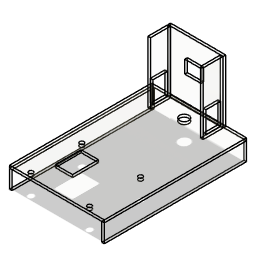
1 (Autodesk Fusion 360 archive; units mm, degrees)
design "placa de acrilico"
Autodesk Fusion 360 part; units mm, degrees
sketch "Esboço1" plane through (0, 0, 0) normal (0, 1, 0) x (1, 0, 0)
  line L0 (0, 0) -> (110, 0)
  line L1 (110, 0) -> (110, 165)
  line L2 (110, 165) -> (0, 165)
  line L3 (0, 165) -> (0, 0)
  circle A0 centre (53.9406, 148.8389) radius 5.4
  line L4 (46.0554, 27.0704) -> (26.0554, 27.0704)
  line L5 (26.0554, 27.0704) -> (26.0554, 57.0704)
  line L6 (26.0554, 57.0704) -> (46.0554, 57.0704)
  line L7 (46.0554, 57.0704) -> (46.0554, 27.0704)
  circle A1 centre (87.4376, 5.4927) radius 2.5
  circle A2 centre (19.4847, 5.405) radius 2.5
  circle A3 centre (19.4835, 64.4469) radius 2.5
  circle A4 centre (87.474, 64.6425) radius 2.5
  dimension "d1" = 110
  dimension "d2" = 165
  dimension "d4" = 10.8
  dimension "d9" = 20
  dimension "d10" = 30
  dimension "d13" = 5
  dimension "d16" = 5
  dimension "d19" = 5
  dimension "d23" = 5
  constraint horizontal L0
  constraint vertical L1
  constraint horizontal L2
  constraint vertical L3
  constraint coincident L0.start L3.end
  constraint horizontal L4
  constraint vertical L5
  constraint horizontal L6
  constraint vertical L7
  measures "d1" distance of L0.start L0.end
  measures "d2" distance of L0.start L2.end
  measures "d4" diameter of A0
  measures "d9" distance of L4.start L4.end
  measures "d10" distance of L4.end L5.end
  measures "d13" diameter of A1
  measures "d16" diameter of A2
  measures "d19" diameter of A3
  measures "d23" diameter of A4
extrude "Extrusão1" add sketch "Esboço1" along normal blind 3 makes body 1
sketch "Esboço2" plane through (0, 0, 0) normal (0, 1, 0) x (1, 0, 0)
  line L0 (120, 0) -> (141, 0)
  line L1 (141, 0) -> (141, 165)
  line L2 (141, 165) -> (120, 165)
  line L3 (120, 165) -> (120, 0)
  dimension "d26" = 21
  dimension "d27" = 165
  constraint horizontal L0
  constraint vertical L1
  constraint horizontal L2
  constraint vertical L3
  measures "d26" distance of L0.start L0.end
  measures "d27" distance of L0.end L1.end
extrude "Extrusão2" add sketch "Esboço2" along normal blind 3 separate body makes body 2
sketch "Esboço3" plane through (0, 0, 0) normal (0, 1, 0) x (1, 0, 0)
  line L0 (150, 0) -> (171, 0)
  line L1 (171, 0) -> (171, 165)
  line L2 (171, 165) -> (150, 165)
  line L3 (150, 165) -> (150, 0)
  dimension "d30" = 21
  dimension "d31" = 165
  constraint horizontal L0
  constraint vertical L1
  constraint horizontal L2
  constraint vertical L3
  measures "d30" distance of L0.start L0.end
  measures "d31" distance of L0.start L2.end
extrude "Extrusão3" add sketch "Esboço3" along normal blind 3 separate body makes body 3
move_body "Mover1" bodies 3 to x (0, -1, 0) y (1, 0, 0) z (0, 0, 1) at (0.0251, 149.951, 0.0481)
move_body "Mover2" bodies 2 to x (0, -1, 0) y (1, 0, 0) z (0, 0, 1) at (107.0123, 119.9798, 0)
sketch "Esboço4" plane through (0, 0, 0) normal (0, 1, 0) x (1, 0, 0)
  line L0 (0.0988, 170.3714) -> (22.0988, 170.3714)
  line L1 (22.0988, 170.3714) -> (86.0988, 170.3714)
  line L2 (86.0988, 170.3714) -> (86.0988, 242.3714)
  line L3 (22.0988, 170.3714) -> (22.0988, 242.3714)
  line L4 (22.0988, 242.3714) -> (86.0988, 242.3714)
  line L5 (41.605, 217.3714) -> (60.605, 217.3714)
  line L6 (41.605, 217.3714) -> (41.605, 202.3714)
  line L7 (60.605, 217.3714) -> (60.605, 202.3714)
  line L8 (41.605, 202.3714) -> (60.605, 202.3714)
  dimension "d34" = 22
  dimension "d35" = 64
  dimension "d36" = 72
  dimension "d37" = 72
  dimension "d44" = 19
  dimension "d46" = 15
  dimension "d47" = 15
  constraint horizontal L0
  constraint parallel L0 L1
  constraint perpendicular L1 L2
  constraint perpendicular L0 L3
  constraint perpendicular L5 L6
  constraint perpendicular L5 L7
  measures "d34" distance of L0.start L0.end
  measures "d35" distance of L0.end L1.end
  measures "d36" distance of L1.end L2.end
  measures "d37" distance of L0.end L3.end
  measures "d44" distance of L5.start L5.end
  measures "d46" distance of L5.start L6.end
  measures "d47" distance of L5.end L7.end
extrude "Extrusão4" add sketch "Esboço4" along normal blind 3 separate body makes body 4
move_body "Mover3" bodies 4 to x (1, 0, 0) y (0, 1, 0) z (0, 0, 1) at (0, 0, 5.0419)
move_body "Mover4" bodies 4 to x (1, 0, 0) y (0, 1, 0) z (0, 0, 1) at (0, 0, 0.1848)
sketch "Esboço5" plane through (0, 3, 0) normal (0, 1, 0) x (-1, 0, 0)
  line L0 (-41.605, -197.1446) -> (-41.605, -212.1446)
  line L1 (-41.605, -212.1446) -> (-60.605, -212.1446)
  line L2 (-60.605, -212.1446) -> (-60.605, -197.1446)
  line L3 (-60.605, -197.1446) -> (-41.605, -197.1446)
  line L4 (-22.0988, -165.1446) -> (-86.0988, -165.1446)
  line L5 (-86.0988, -165.1446) -> (-86.0988, -237.1446)
  line L6 (-86.0988, -237.1446) -> (-22.0988, -237.1446)
  line L7 (-22.0988, -237.1446) -> (-22.0988, -165.1446)
  line L8 (-159.9044, -164.752) -> (-182.9044, -164.752)
  line L9 (-182.9044, -164.752) -> (-182.9044, -236.752)
  line L10 (-182.9044, -236.752) -> (-159.9044, -236.752)
  line L11 (-159.9044, -236.752) -> (-159.9044, -164.752)
  line L12 (-163.1314, -168.0719) -> (-180.1314, -168.0719)
  line L13 (-180.1314, -168.0719) -> (-180.1314, -193.0719)
  line L14 (-180.1314, -193.0719) -> (-163.1314, -193.0719)
  line L15 (-163.1314, -193.0719) -> (-163.1314, -168.0719)
  line L16 (-144.4837, -168.5234) -> (-144.4837, -240.5234)
  line L17 (-121.4837, -240.5234) -> (-121.4837, -168.5234)
  line L18 (-141.7107, -171.8432) -> (-141.7107, -196.8432)
  line L19 (-124.7107, -171.8432) -> (-141.7107, -171.8432)
  line L20 (-141.7107, -196.8432) -> (-124.7107, -196.8432)
  line L21 (-121.4837, -168.5234) -> (-144.4837, -168.5234)
  line L22 (-144.4837, -240.5234) -> (-121.4837, -240.5234)
  line L23 (-124.7107, -196.8432) -> (-124.7107, -171.8432)
  dimension "d50" = 23
  dimension "d51" = 72
  dimension "d55" = 17
  dimension "d56" = 25
  dimension "d57" = 23
  dimension "d58" = 72
  dimension "d59" = 17
  dimension "d60" = 25
  constraint horizontal L8
  constraint vertical L9
  constraint horizontal L10
  constraint vertical L11
  constraint horizontal L12
  constraint vertical L13
  constraint horizontal L14
  constraint vertical L15
  constraint horizontal L21
  constraint vertical L16
  constraint horizontal L22
  constraint vertical L17
  constraint horizontal L19
  constraint vertical L18
  constraint horizontal L20
  constraint vertical L23
  measures "d50" distance of L8.start L8.end
  measures "d51" distance of L8.start L10.end
  measures "d55" distance of L12.start L12.end
  measures "d56" distance of L12.start L14.end
  measures "d57" distance of L16.start L17.end
  measures "d58" distance of L17.end L17.start
  measures "d59" distance of L18.start L19.start
  measures "d60" distance of L19.start L20.end
extrude "Extrusão5" add sketch "Esboço5" along normal blind 3 separate body contours L8 L9 L10 L11 makes body 5
extrude "Extrusão6" add sketch "Esboço5" along normal blind 3 separate body contours L16 L17 L21 L22 makes body 6
move_body "Mover5" bodies 5 to x (0, 1, 0) y (-1, 0, 0) z (0, 0, 1) at (27.3401, -183.0555, -0.1604)
move_body "Mover6" bodies 5 to x (1, 0, 0) y (0, 1, 0) z (0, 0, 1) at (0.7325, 0, -0.2616)
move_body "Mover7" bodies 5 to x (1, 0, 0) y (0, 1, 0) z (0, 0, 1) at (-0.0523, 0.157, 0)
move_body "Mover8" bodies 6 to x (0, -1, 0) y (1, 0, 0) z (0, 0, 1) at (83.0995, 124.4103, 3.4941)
move_body "Mover9" bodies 4 5 6 to x (1, 0, 0) y (0, 0, 1) z (0, -1, 0) at (-0.3031, -161.9207, -141.7867)
move_body "Mover10" bodies 6 to x (1, 0, 0) y (0, 1, 0) z (0, 0, 1) at (0, 2.7335, -4.2826)
move_body "Mover11" bodies 6 to x (1, 0, 0) y (0, 1, 0) z (0, 0, 1) at (0, -2.6483, 1.4345)
move_body "Mover12" bodies 3 5 1 6 2 4 to x (1, 0, 0) y (0, 1, 0) z (0, 0, 1) at (135.7751, 64.3146, 24.9729)
move_body "Mover13" bodies 6 to x (1, 0, 0) y (0, 1, 0) z (0, 0, 1) at (-3.0347, -0.002, 26.0381)
move_body "Mover14" bodies 5 to x (1, 0, 0) y (0, 1, 0) z (0, 0, 1) at (0, -0.2162, 26.1575)
move_body "Mover15" bodies 5 4 6 to x (1, 0, 0) y (0, 1, 0) z (0, 0, 1) at (0.1081, -0.9435, -23.1586)
copy_body "Corpo -> Componente1" bodies 1 removing the originals makes body 7 in component "Component"
copy_body "Corpo -> Componente2" bodies 2 removing the originals makes body 8 in component "Component'"
copy_body "Corpo -> Componente3" bodies 3 removing the originals makes body 9 in component "Component''"
copy_body "Corpo -> Componente4" bodies 4 removing the originals makes body 10 in component "Component'''"
copy_body "Corpo -> Componente5" bodies 5 removing the originals makes body 11 in component "Component''''"
copy_body "Corpo -> Componente6" bodies 6 removing the originals makes body 12 in component "Component'''''"
component "Component" placed x (1, 0, 0) y (0, 1, 0) z (0, 0, 1) at (0, 0, 0)
component "Component'" placed x (1, 0, 0) y (0, 1, 0) z (0, 0, 1) at (0, 0, 0)
component "Component''" placed x (1, 0, 0) y (0, 1, 0) z (0, 0, 1) at (0, 0, 0)
component "Component'''" placed x (1, 0, 0) y (0, 1, 0) z (0, 0, 1) at (0, 0, 0)
component "Component''''" placed x (1, 0, 0) y (0, 1, 0) z (0, 0, 1) at (0, 0, 0)
component "Component'''''" placed x (1, 0, 0) y (0, 1, 0) z (0, 0, 1) at (0, 0, 0)

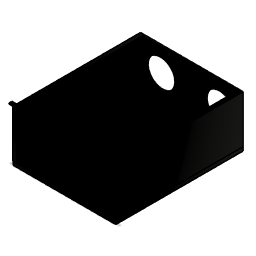
design "case ultrassonico"
Autodesk Fusion 360 part; units mm, degrees
sketch "Esboço1" plane through (0, 0, 0) normal (0, 1, 0) x (1, 0, 0)
  line L0 (0, 0) -> (50, 0)
  line L1 (0, 0) -> (0, 25)
  line L2 (0, 25) -> (50, 25)
  line L3 (50, 0) -> (50, 25)
  dimension "d1" = 50
  dimension "d2" = 25
  dimension "d3" = 50
  constraint coincident L0.start L1.start
  constraint horizontal L0
  constraint perpendicular L0 L1
  constraint perpendicular L1 L2
  measures "d1" distance of L0.start L0.end
  measures "d2" distance of L0.start L1.end
  measures "d3" distance of L1.end L2.end
extrude "Extrusão1" add sketch "Esboço1" along normal blind 1 makes body 1
hole "Furo1" at (48.8081, 0, -23.5629) direction (0, 1, 0) diameter 1.8 depth 3 tip angle 118 bodies 1
hole "Furo2" at (1.4563, 0, -23.59) direction (0, 1, 0) diameter 1.8 depth 3 tip angle 118 bodies 1
hole "Furo3" at (1.4485, 0, -1.5957) direction (0, 1, 0) diameter 1.8 depth 3 tip angle 118 bodies 1
hole "Furo4" at (48.7733, 0, -1.5876) direction (0, 1, 0) diameter 1.8 depth 3 tip angle 118 bodies 1
hole "Furo5" at (40.5295, 1, -12.6422) direction (0, -1, 0) diameter 15 depth 3 tip angle 118 bodies 1
hole "Furo6" at (9.5185, 1, -12.5143) direction (0, -1, 0) diameter 15 depth 3 tip angle 118 bodies 1
sketch "Esboço2" plane through (0, 0, 0) normal (0, 1, 0) x (1, 0, 0)
hole "Furo7" at (19.0736, 1, -6.6825) direction (0, -1, 0) diameter 2 depth 3 tip angle 118 bodies 1
hole "Furo8" at (21.3988, 1, -6.6049) direction (0, -1, 0) diameter 2 depth 3 tip angle 118 bodies 1
hole "Furo9" at (23.8843, 1, -6.6851) direction (0, -1, 0) diameter 2 depth 3 tip angle 118 bodies 1
hole "Furo10" at (26.4099, 1, -6.7252) direction (0, -1, 0) diameter 2 depth 3 tip angle 118 bodies 1
sketch "Esboço3" plane through (0, 0, 0) normal (0, 1, 0) x (1, 0, 0)
  line L0 (0, -40) -> (67.2, -40)
  line L1 (0, 25) -> (0, 0)
  line L2 (0, -40) -> (0, -15)
  line L3 (0, -15) -> (67.2, -15)
  line L4 (67.2, -15) -> (67.2, -40)
  line L5 (4.8529, -44.5004) -> (72.0529, -44.5004)
  line L6 (4.8529, -69.5004) -> (72.0529, -69.5004)
  line L7 (4.8529, -44.5004) -> (4.8529, -69.5004)
  line L8 (72.0529, -44.5004) -> (72.0529, -69.5004)
  dimension "d37" = 25
  dimension "d38" = 25
  dimension "d39" = 67.2
  dimension "d40" = 25
  dimension "d41" = 67.2
  constraint horizontal L0
  constraint perpendicular L0 L2
  constraint perpendicular L2 L3
  constraint horizontal L6
  constraint perpendicular L6 L7
  constraint perpendicular L6 L8
  measures "d37" distance of L1.start L1.end
  measures "d38" distance of L0.start L2.end
  measures "d39" distance of L2.end L3.end
  measures "d40" distance of L5.start L6.start
  measures "d41" distance of L5.start L5.end
extrude "Extrusão2" add sketch "Esboço3" along normal blind 2 separate body contours L0 L2 L3 L4 makes body 2
extrude "Extrusão3" add sketch "Esboço3" along normal blind 2 separate body contours L5 L6 L7 L8 makes body 3
move_body "Mover1" bodies 1 to x (1, 0, 0) y (0, 0, 1) z (0, -1, 0) at (0, -1.7077, -25.5977)
move_body "Mover2" bodies 3 to x (0, 0, -1) y (-1, 0, 0) z (0, 1, 0) at (-0.0034, -46.234, 46.4307)
move_body "Mover3" bodies 2 to x (0, 0, -1) y (1, 0, 0) z (0, -1, 0) at (50.0007, 38.304, 41.6132)
sketch "Esboço4" plane through (0, 0, 0) normal (0, 1, 0) x (1, 0, 0)
  line L0 (-40, 0) -> (-40, 10)
  line L1 (-40, 10) -> (-30, 10)
  line L2 (-30, 10) -> (-30, 5)
  line L3 (-30, 5) -> (-35, 5)
  line L4 (-35, 5) -> (-35, 0)
  line L5 (-35, 0) -> (-40, 0)
  constraint vertical L0
  constraint perpendicular L0 L1
  constraint perpendicular L1 L2
  constraint perpendicular L2 L3
  constraint perpendicular L3 L4
  constraint perpendicular L0 L5
sketch "Esboço5" plane through (0, 0, 0) normal (0, 1, 0) x (1, 0, 0)
  line L0 (-4.2157, -41.4575, -0.4132) -> (-8.1992, -41.4575, -0.4132)
  line L1 (-8.1992, -41.4575, -0.4132) -> (-8.1992, -39.8904, -0.4132)
  line L2 (-8.1992, -39.8904, -0.4132) -> (-4.1992, -39.8904, -0.4132)
  line L3 (-4.1992, -39.8904, -0.4132) -> (-4.2157, -41.4575, -0.4132)
  dimension "d48" = 3.9836
  dimension "d49" = 1.5671
extrude "Extrusão5" add sketch "Esboço5" along normal blind 0.5 separate body contours L0 L1 L2 L3 in plane through (0, -0.4132, 0) normal (0, 1, 0) makes body 4
move_body "Mover5" bodies 4 to x (1, 0, 0) y (0, 1, 0) z (0, 0, 1) at (4.2199, 23.6968, 0.1453)
sketch "Esboço6" plane through (0, 0, 0) normal (0, 1, 0) x (1, 0, 0)
  line L0 (50.0163, -44.0903) -> (54.0003, -44.0903)
  line L1 (50.0163, -44.0903) -> (50.0163, -42.5233)
  line L2 (50.0163, -42.5233) -> (53.9855, -42.5233)
  line L3 (53.9855, -42.5233) -> (54.0003, -44.0903)
  dimension "d52" = 3.984
  dimension "d53" = 1.567
  constraint horizontal L0
  constraint perpendicular L0 L1
  constraint perpendicular L1 L2
  measures "d52" distance of L0.start L0.end
  measures "d53" distance of L0.start L1.end
extrude "Extrusão6" add sketch "Esboço6" along normal blind 0.5 separate body makes body 5
move_body "Mover6" bodies 5 to x (1, 0, 0) y (0, 1, 0) z (0, 0, 1) at (-0.0037, 23.3, -2.5739)
move_body "Mover7" bodies 5 to x (1, 0, 0) y (0, 1, 0) z (0, 0, 1) at (-0.0106, 0, 0.0823)
sketch "Esboço7" plane through (0, 0, 0) normal (0, 1, 0) x (1, 0, 0)
  line L0 (0, 25.5977) -> (50, 25.5977)
  line L1 (52.0007, -41.6132) -> (52.0007, 25.5868)
  line L2 (70, 0) -> (120, 0)
  line L3 (120, 0) -> (120, -67.2)
  line L4 (120, -67.2) -> (70, -67.2)
  line L5 (70, -67.2) -> (70, 0)
  dimension "d56" = 50
  dimension "d57" = 67.2
  dimension "d58" = 67.2
  dimension "d59" = 50
  constraint horizontal L2
  constraint vertical L3
  constraint horizontal L4
  constraint vertical L5
  measures "d56" distance of L0.start L0.end
  measures "d57" distance of L1.start L1.end
  measures "d58" distance of L2.start L4.end
  measures "d59" distance of L2.start L2.end
sketch "Esboço8" plane through (0, 0, 0) normal (0, 1, 0) x (1, 0, 0)
  line L0 (-30, 0) -> (-84, 0)
  line L1 (-84, 0) -> (-84, 67)
  line L2 (-84, 67) -> (-30, 67)
  line L3 (-30, 67) -> (-30, 0)
  dimension "d66" = 67
  dimension "d67" = 54
  constraint horizontal L0
  constraint vertical L1
  constraint horizontal L2
  constraint vertical L3
  measures "d66" distance of L0.start L2.end
  measures "d67" distance of L0.start L0.end
extrude "Extrusão8" add sketch "Esboço8" along normal blind 2 separate body makes body 6
move_body "Mover10" bodies 6 to x (1, 0, 0) y (0, 1, 0) z (0, 0, 1) at (82.019, -3.6652, 41.4629)
copy_body "Corpo -> Componente1" bodies 1 removing the originals makes body 7 in component "Component"
copy_body "Corpo -> Componente2" bodies 2 removing the originals makes body 8 in component "Component'"
copy_body "Corpo -> Componente3" bodies 3 removing the originals makes body 9 in component "Component''"
copy_body "Corpo -> Componente4" bodies 4 removing the originals makes body 10 in component "Component'''"
copy_body "Corpo -> Componente5" bodies 5 removing the originals makes body 11 in component "Component''''"
copy_body "Corpo -> Componente6" bodies 6 removing the originals makes body 12 in component "Component'''''"
move_body "Mover1'" bodies 9 to x (1, 0, 0) y (0, 1, 0) z (0, 0, 1) at (165.5243, 14.3172, -24.596) in component "Component''"
move_body "Mover1''" bodies 11 to x (1, 0, 0) y (0, 1, 0) z (0, 0, 1) at (165.5243, 14.3172, -24.596) in component "Component''''"
move_body "Mover1'''" bodies 12 to x (1, 0, 0) y (0, 1, 0) z (0, 0, 1) at (165.5243, 14.3172, -24.596) in component "Component'''''"
move_body "Mover1''''" bodies 10 to x (1, 0, 0) y (0, 1, 0) z (0, 0, 1) at (165.5243, 14.3172, -24.596) in component "Component'''"
move_body "Mover1'''''" bodies 8 to x (1, 0, 0) y (0, 1, 0) z (0, 0, 1) at (165.5243, 14.3172, -24.596) in component "Component'"
move_body "Mover1''''''" bodies 7 to x (1, 0, 0) y (0, 1, 0) z (0, 0, 1) at (165.5243, 14.3172, -24.596) in component "Component"
component "Component" placed x (1, 0, 0) y (0, 1, 0) z (0, 0, 1) at (0, 0, 0)
component "Component'" placed x (1, 0, 0) y (0, 1, 0) z (0, 0, 1) at (0, 0, 0)
component "Component''" placed x (1, 0, 0) y (0, 1, 0) z (0, 0, 1) at (0, 0, 0)
component "Component'''" placed x (1, 0, 0) y (0, 1, 0) z (0, 0, 1) at (0, 0, 0)
component "Component''''" placed x (1, 0, 0) y (0, 1, 0) z (0, 0, 1) at (0, 0, 0)
component "Component'''''" placed x (1, 0, 0) y (0, 1, 0) z (0, 0, 1) at (0, 0, 0)

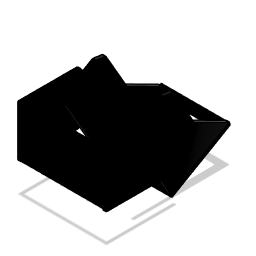
design "estrutura da camera"
Autodesk Fusion 360 part; units mm, degrees
sketch "Esboço1" plane through (0, 0, 0) normal (0, 1, 0) x (1, 0, 0)
  line L0 (0, 0) -> (0, 25.6)
  line L1 (0, 25.6) -> (30, 25.6)
  line L2 (30, 25.6) -> (35.5763, 17.2991)
  line L3 (35.5763, 17.2991) -> (35.5763, 7.2991)
  line L4 (35.5763, 7.2991) -> (28.6904, 0.0476)
  line L5 (0, 0) -> (28.6904, 0.0476)
  line L6 (0.2721, -30.9273) -> (0.2721, -5.3273)
  line L7 (35.8484, -13.6282) -> (35.8484, -23.6282)
  line L8 (30.2721, -5.3273) -> (35.8484, -13.6282)
  line L9 (35.8484, -23.6282) -> (28.9625, -30.8797)
  line L10 (0.2721, -5.3273) -> (30.2721, -5.3273)
  line L11 (0.2721, -30.9273) -> (28.9625, -30.8797)
  point P0 (0.2721, -30.9273)
  dimension "d1" = 25.6
  dimension "d13" = 30
  dimension "d14" = 10
  dimension "d15" = 10
  dimension "d16" = 10
  dimension "d17" = 25.6
  dimension "d18" = 30
  dimension "d19" = 10
  dimension "d20" = 10
  dimension "d21" = 10
  constraint coincident L0.start L5.start
  constraint vertical L0
  constraint perpendicular L0 L1
  constraint perpendicular L1 L3
  constraint coincident P0 L6.start
  constraint vertical L6
  constraint perpendicular L6 L10
  constraint perpendicular L7 L10
  measures "d1" distance of L0.start L0.end
  measures "d13" distance of L0.end L1.end
  measures "d14" distance of L1.end L2.end
  measures "d15" distance of L2.end L3.end
  measures "d16" distance of L3.end L4.end
  measures "d17" distance of P0 L6.end
  measures "d18" distance of L8.start L6.end
  measures "d19" distance of L8.start L7.start
  measures "d20" distance of L7.start L7.end
  measures "d21" distance of L9.end L7.end
extrude "Extrusão1" add sketch "Esboço1" along normal blind 1.7 contours L0 L1 L2 L3 L4 L5 makes body 1
extrude "Extrusão2" add sketch "Esboço1" along normal blind 1.7 separate body contours L6 L7 L8 L9 L10 L11 makes body 2
sketch "Esboço2" plane through (0, 0, 0) normal (0, 1, 0) x (1, 0, 0)
  line L0 (50, 0) -> (94.3, 0)
  line L1 (94.3, 0) -> (94.3, 25)
  line L2 (94.3, 25) -> (50, 25)
  line L3 (50, 25) -> (50, 0)
  dimension "d26" = 44.3
  dimension "d27" = 25
  constraint horizontal L0
  constraint vertical L1
  constraint horizontal L2
  constraint vertical L3
  measures "d26" distance of L0.start L0.end
  measures "d27" distance of L0.start L2.end
extrude "Extrusão3" add sketch "Esboço2" along normal blind 1.7 separate body makes body 3
move_body "Mover1" bodies 2 to x (0, 0, 1) y (1, 0, 0) z (0, 1, 0) at (14.9891, -4.8114, 5.0553)
move_body "Mover2" bodies 3 to x (1, 0, 0) y (0, 0, 1) z (0, -1, 0) at (-35.3599, 1.1388, 5.3832)
move_body "Mover3" bodies 3 to x (1, 0, 0) y (0, 1, 0) z (0, 0, 1) at (0.6743, -0.0545, 0)
move_body "Mover4" bodies 1 to x (0, 0, 1) y (-1, 0, 0) z (0, -1, 0) at (59.6914, 0.4143, 4.9875)
move_body "Mover5" bodies 1 to x (1, 0, 0) y (0, 1, 0) z (0, 0, 1) at (0, 0.3354, 0.5385)
sketch "Esboço3" plane through (0, 0, 0) normal (0, 1, 0) x (1, 0, 0)
  line L0 (-26.5558, -20.9139) -> (7.4442, -20.9139)
  line L1 (7.4442, -20.9139) -> (7.4442, 13.0861)
  line L2 (7.4442, 13.0861) -> (-26.5558, 13.0861)
  line L3 (-26.5558, 13.0861) -> (-26.5558, -20.9139)
  line L4 (-22.5558, -16.9139) -> (3.21, -16.9139)
  line L5 (-22.5558, -16.9139) -> (-22.5558, 9.1437)
  line L6 (-22.5558, 9.1437) -> (3.21, 9.0861)
  line L7 (3.21, -16.9139) -> (3.21, 9.0861)
  dimension "d30" = 34
  dimension "d31" = 34
  constraint horizontal L0
  constraint vertical L1
  constraint horizontal L2
  constraint vertical L3
  constraint perpendicular L3 L4
  constraint vertical L7
  measures "d30" distance of L0.start L0.end
  measures "d31" distance of L0.start L2.end
extrude "Extrusão4" add sketch "Esboço3" along normal blind 1.7 separate body makes body 4
sketch "Esboço4" plane through (0, 0, 0) normal (0, 1, 0) x (1, 0, 0)
  line L0 (68.4509, 0.0237) -> (102.4509, 0.0237)
  line L1 (68.4509, 0.0237) -> (68.4509, 38.0237)
  line L2 (68.4509, 38.0237) -> (72.4483, 41.0271)
  line L3 (72.4483, 41.0271) -> (87.4483, 41.0271)
  line L4 (87.4483, 41.0271) -> (91.3736, 37.93)
  line L5 (91.3736, 37.93) -> (91.3736, 16.93)
  line L6 (102.4509, 0.0237) -> (91.3736, 16.93)
  line L7 (109.5977, 1.8719) -> (109.5977, 39.8719)
  line L8 (109.5977, 1.8719) -> (143.5977, 1.8719)
  line L9 (109.5977, 39.8719) -> (113.5952, 42.8753)
  line L10 (132.5204, 39.7782) -> (132.5204, 18.7782)
  line L11 (113.5952, 42.8753) -> (128.5952, 42.8753)
  line L12 (143.5977, 1.8719) -> (132.5204, 18.7782)
  line L13 (128.5952, 42.8753) -> (132.5204, 39.7782)
  dimension "d38" = 34
  dimension "d45" = 38
  dimension "d46" = 5
  dimension "d47" = 15
  dimension "d48" = 5
  dimension "d49" = 21
  dimension "d50" = 20.212
  dimension "d51" = 34
  dimension "d52" = 38
  dimension "d53" = 5
  dimension "d54" = 15
  dimension "d55" = 5
  dimension "d56" = 21
  dimension "d57" = 20.212
  constraint horizontal L0
  constraint perpendicular L0 L1
  constraint horizontal L3
  constraint perpendicular L3 L5
  constraint horizontal L8
  constraint perpendicular L7 L8
  constraint horizontal L11
  constraint perpendicular L10 L11
  measures "d38" distance of L0.start L0.end
  measures "d45" distance of L0.start L1.end
  measures "d46" distance of L1.end L2.end
  measures "d47" distance of L2.end L3.end
  measures "d48" distance of L3.end L4.end
  measures "d49" distance of L4.end L5.end
  measures "d50" distance of L0.end L5.end
  measures "d51" distance of L7.start L8.end
  measures "d52" distance of L7.end L7.start
  measures "d53" distance of L7.end L9.end
  measures "d54" distance of L9.end L11.end
  measures "d55" distance of L11.end L10.start
  measures "d56" distance of L10.end L10.start
  measures "d57" distance of L10.end L8.end
extrude "Extrusão5" add sketch "Esboço4" along normal blind 1.7 separate body contours L0 L1 L2 L3 L4 L5 L6 makes body 5
extrude "Extrusão6" add sketch "Esboço4" along normal blind 1.7 separate body contours L7 L8 L9 L10 L11 L12 L13 makes body 6
move_body "Mover6" bodies 6 to x (0, 0.5, 0.866025) y (-1, 0, 0) z (0, -0.866025, 0.5) at (54.8777, -70.4617, -51.5725)
move_body "Mover7" bodies 4 to x (1, 0, 0) y (0, 0.866025, -0.5) z (0, 0.5, 0.866025) at (45.637, -7.2442, 53.7843)
move_body "Mover8" bodies 5 to x (0, 0.5, 0.866025) y (-1, 0, 0) z (0, -0.866025, 0.5) at (20.5759, -46.6633, -17.2925)
move_body "Mover9" bodies 2 1 3 4 6 5 to x (-1, 0, 0) y (0, 1, 0) z (0, 0, -1) at (227.1311, 112.3048, -134.6357)
copy_body "Corpo -> Componente1" bodies 1 removing the originals makes body 7 in component "Component"
copy_body "Corpo -> Componente2" bodies 2 removing the originals makes body 8 in component "Component'"
copy_body "Corpo -> Componente3" bodies 3 removing the originals makes body 9 in component "Component''"
copy_body "Corpo -> Componente4" bodies 4 removing the originals makes body 10 in component "Component'''"
copy_body "Corpo -> Componente5" bodies 5 removing the originals makes body 11 in component "Component''''"
copy_body "Corpo -> Componente6" bodies 6 removing the originals makes body 12 in component "Component'''''"
move_body "Mover1'" bodies 8 to x (1, 0, 0) y (0, 1, 0) z (0, 0, 1) at (3.9237, -102.3134, 41.3543) in component "Component'"
move_body "Mover1''" bodies 9 to x (1, 0, 0) y (0, 1, 0) z (0, 0, 1) at (3.9237, -102.3134, 41.3543) in component "Component''"
move_body "Mover1'''" bodies 10 to x (1, 0, 0) y (0, 1, 0) z (0, 0, 1) at (3.9237, -102.3134, 41.3543) in component "Component'''"
move_body "Mover1''''" bodies 11 to x (1, 0, 0) y (0, 1, 0) z (0, 0, 1) at (3.9237, -102.3134, 41.3543) in component "Component''''"
move_body "Mover1'''''" bodies 12 to x (1, 0, 0) y (0, 1, 0) z (0, 0, 1) at (3.9237, -102.3134, 41.3543) in component "Component'''''"
move_body "Mover1''''''" bodies 7 to x (1, 0, 0) y (0, 1, 0) z (0, 0, 1) at (3.9237, -102.3134, 41.3543) in component "Component"
component "Component" placed x (1, 0, 0) y (0, 1, 0) z (0, 0, 1) at (0, 0, 0)
component "Component'" placed x (1, 0, 0) y (0, 1, 0) z (0, 0, 1) at (0, 0, 0)
component "Component''" placed x (1, 0, 0) y (0, 1, 0) z (0, 0, 1) at (0, 0, 0)
component "Component'''" placed x (1, 0, 0) y (0, 1, 0) z (0, 0, 1) at (0, 0, 0)
component "Component''''" placed x (1, 0, 0) y (0, 1, 0) z (0, 0, 1) at (0, 0, 0)
component "Component'''''" placed x (1, 0, 0) y (0, 1, 0) z (0, 0, 1) at (0, 0, 0)

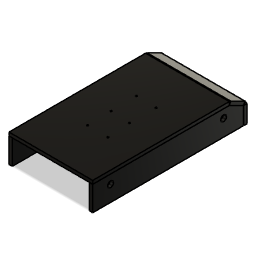
design "base do robo"
Autodesk Fusion 360 part; units mm, degrees
sketch "Esboço1" plane through (0, 0, 0) normal (0, 1, 0) x (1, 0, 0)
  line L0 (0, 0) -> (100, 0)
  line L1 (100, 0) -> (100, 163.058)
  line L2 (100, 163.058) -> (0, 163.058)
  line L3 (0, 163.058) -> (0, 0)
  dimension "d1" = 100
  dimension "d2" = 163.058
  constraint horizontal L0
  constraint vertical L1
  constraint horizontal L2
  constraint vertical L3
  constraint coincident L0.start L3.end
  measures "d1" distance of L0.start L0.end
  measures "d2" distance of L0.start L2.end
extrude "Extrusão1" add sketch "Esboço1" along normal blind 4 makes body 1
sketch "Esboço2" plane through (0, 0, 0) normal (1, 0, 0) x (0, 0, -1)
  line L0 (162.9842, -70.1865) -> (-0.0738, -70.1865)
  line L1 (-0.0738, -70.1865) -> (-0.0738, -99.5355)
  line L2 (-0.0738, -99.5355) -> (179.9262, -99.5355)
  line L3 (179.9262, -99.5355) -> (179.9262, -78.6355)
  line L4 (179.9262, -78.6355) -> (162.9233, -70.1561)
  line L5 (180.6723, -63.1652) -> (180.6723, -42.2652)
  line L6 (163.7303, -33.8162) -> (0.6723, -33.8162)
  line L7 (180.6723, -42.2652) -> (163.6694, -33.7858)
  line L8 (0.6723, -33.8162) -> (0.6723, -63.1652)
  line L9 (0.6723, -63.1652) -> (180.6723, -63.1652)
  dimension "d11" = 163.058
  dimension "d13" = 29.349
  dimension "d14" = 180
  dimension "d15" = 20.9
  dimension "d16" = 19
  dimension "d17" = 163.058
  dimension "d18" = 29.349
  dimension "d19" = 180
  dimension "d20" = 20.9
  dimension "d21" = 19
  constraint perpendicular L0 L1
  constraint perpendicular L1 L2
  constraint perpendicular L2 L3
  constraint perpendicular L6 L8
  constraint perpendicular L8 L9
  constraint perpendicular L5 L9
  measures "d11" distance of L0.start L0.end
  measures "d13" distance of L0.end L1.end
  measures "d14" distance of L1.end L2.end
  measures "d15" distance of L2.end L3.end
  measures "d16" distance of L3.end L4.end
  measures "d17" distance of L6.start L6.end
  measures "d18" distance of L8.end L6.end
  measures "d19" distance of L8.end L5.start
  measures "d20" distance of L5.end L5.start
  measures "d21" distance of L5.end L7.end
extrude "Extrusão2" add sketch "Esboço2" along normal blind 4 separate body contours L0 L1 L2 L3 L4 makes body 2
move_body "Mover1" bodies 2 to x (1, 0, 0) y (0, 1, 0) z (0, 0, 1) at (0.0284, 70.1631, -0.0401)
sketch "Esboço3" plane through (0, 0, 0) normal (1, 0, 0) x (0, 0, -1)
  line L0 (-0.0337, -0.0235) -> (-0.0337, -29.3725)
  line L1 (-0.0337, -29.3725) -> (179.9663, -29.3725)
  line L2 (-0.0337, -59.9681) -> (163.0243, -59.9681)
  line L3 (-0.0337, -59.9681) -> (-0.0337, -89.3171)
  line L4 (-0.0337, -89.3171) -> (179.9663, -89.3171)
  line L5 (179.9663, -89.3171) -> (179.9663, -68.4171)
  line L6 (179.9663, -68.4171) -> (162.9483, -59.9681)
  dimension "d24" = 29.349
  dimension "d25" = 180
  dimension "d26" = 163.058
  dimension "d27" = 29.349
  dimension "d28" = 180
  dimension "d29" = 20.9
  dimension "d30" = 19
  constraint perpendicular L0 L2
  constraint perpendicular L2 L3
  constraint perpendicular L3 L4
  constraint perpendicular L4 L5
  constraint coincident L2 L6.end
  measures "d24" distance of L0.start L0.end
  measures "d25" distance of L0.end L1.end
  measures "d26" distance of L2.start L2.end
  measures "d27" distance of L2.start L3.end
  measures "d28" distance of L3.end L4.end
  measures "d29" distance of L4.end L5.end
  measures "d30" distance of L5.end L6.end
extrude "Extrusão3" add sketch "Esboço3" along normal blind 4 separate body makes body 3
move_body "Mover2" bodies 3 to x (1, 0, 0) y (0, 1, 0) z (0, 0, 1) at (96.0394, 59.9598, 0.0597)
sketch "Esboço4" plane through (0, 0, 0) normal (0, 1, 0) x (1, 0, 0)
  line L0 (0, -20) -> (-100, -20)
  line L1 (-100, -20) -> (-100, -39)
  line L2 (-100, -39) -> (0, -39)
  line L3 (0, -39) -> (0, -20)
  dimension "d33" = 100
  dimension "d34" = 19
  constraint horizontal L0
  constraint vertical L1
  constraint horizontal L2
  constraint vertical L3
  measures "d33" distance of L0.start L0.end
  measures "d34" distance of L0.start L2.end
extrude "Extrusão4" add sketch "Esboço4" along normal blind 4 separate body makes body 4
move_body "Mover3" bodies 4 to x (1, 0, 0) y (0, 0.906308, -0.422618) z (0, 0.422618, 0.906308) at (100.1797, -16.7473, -198.2869)
sketch "Esboço5" plane through (0, 0, 0) normal (0, 1, 0) x (1, 0, 0)
  line L0 (0, -40) -> (100, -40)
  line L1 (100, -40) -> (100, -19.1)
  line L2 (100, -19.1) -> (0, -19.1)
  line L3 (0, -19.1) -> (0, -40)
  dimension "d37" = 100
  dimension "d38" = 20.9
  constraint horizontal L0
  constraint vertical L1
  constraint horizontal L2
  constraint vertical L3
  measures "d37" distance of L0.start L0.end
  measures "d38" distance of L0.start L2.end
extrude "Extrusão5" add sketch "Esboço5" along normal blind 4 separate body makes body 5
move_body "Mover4" bodies 5 to x (1, 0, 0) y (0, 0, -1) z (0, 1, 0) at (0.2983, -48.3447, -179.9609)
sketch "Esboço6" plane through (0, 0, 0) normal (0, 0, 1) x (1, 0, 0)
sketch "Esboço7" plane through (0, 0, 0) normal (1, 0, 0) x (0, 0, -1)
move_body "Mover5" bodies 4 to x (1, 0, 0) y (0, 0.999657, -0.026177) z (0, 0.026177, 0.999657) at (0, 4.6231, -0.0364)
sketch "Esboço8" plane through (0, 0, 0) normal (1, 0, 0) x (0, 0, -1)
  line L0 (179.9609, -8.3447) -> (183.9609, -8.3447)
  line L1 (179.9183, -8.385) -> (181.7031, -4.8053)
  line L2 (183.9609, -8.3447) -> (179.9609, -8.3447)
  line L3 (181.7031, -4.8053) -> (179.9183, -8.385)
  line L4 (183.9609, -8.3447) -> (181.7031, -4.8053)
  line L5 (183.9609, -8.3447) -> (179.9183, -8.385)
  dimension "d41" = 4
  dimension "d42" = 4
  constraint coincident L0.end L2.start
  constraint coincident L0.start L2.end
  constraint coincident L1.end L3.start
  constraint coincident L1.start L3.end
  measures "d41" distance of L0.start L0.end
  measures "d42" distance of L1.start L1.end
extrude "Extrusão6" add sketch "Esboço8" along normal blind 100 separate body makes body 6
move_body "Mover6" bodies 4 to x (1, 0, 0) y (0, 1, 0) z (0, 0, 1) at (0, -0.0409, 0)
sketch "Esboço9" plane through (0, 0, 0) normal (1, 0, 0) x (0, 0, -1)
  line L0 (163.0672, 3.9976) -> (163.0672, 0.3722)
  line L1 (163.0672, 0.3722) -> (164.6958, 3.6223)
  line L2 (164.6958, 3.6223) -> (163.0672, 3.9976)
  constraint vertical L0
extrude "Extrusão7" add sketch "Esboço9" against normal blind 100 separate body makes body 7
move_body "Mover7" bodies 7 to x (1, 0, 0) y (0, 1, 0) z (0, 0, 1) at (100.0984, -0.0039, -0.0209)
sketch "Esboço10" plane through (0, 0, 0) normal (0, 0, 1) x (1, 0, 0)
hole "Furo1" at (18.0294, -13.5758, -183.9609) direction (0, 0, 1) diameter 2 depth 4 tip angle 118 bodies 5
hole "Furo2" at (18.1336, -22.9531, -183.9609) direction (0, 0, 1) diameter 2 depth 4 tip angle 118 bodies 5
hole "Furo3" at (84.2563, -13.515, -183.9609) direction (0, 0, 1) diameter 2 depth 4 tip angle 118 bodies 5
hole "Furo4" at (84.377, -23.3309, -183.9609) direction (0, 0, 1) diameter 2 depth 4 tip angle 118 bodies 5
hole "Furo5" at (0.0284, -9.9898, -157.2428) direction (1, 0, 0) diameter 7 depth 18 tip angle 118 bodies 2
hole "Furo6" at (0.0284, -9.613, -20.9074) direction (1, 0, 0) diameter 7 depth 18 tip angle 118 bodies 2
hole "Furo7" at (100.0394, -10.5551, -21.2843) direction (-1, 0, 0) diameter 7 depth 18 tip angle 118 bodies 3
hole "Furo8" at (100.0394, -9.8014, -156.2063) direction (-1, 0, 0) diameter 7 depth 18 tip angle 118 bodies 3
hole "Furo9" at (64.3345, 4, -53.704) direction (0, -1, 0) diameter 2 depth 18 tip angle 118 bodies 1
hole "Furo10" at (40.0169, 4, -53.8726) direction (0, -1, 0) diameter 2 depth 18 tip angle 118 bodies 1
hole "Furo11" at (62.3597, 4, -81.2465) direction (0, -1, 0) diameter 2 depth 18 tip angle 118 bodies 1
hole "Furo12" at (39.2799, 4, -82.6492) direction (0, -1, 0) diameter 2 depth 18 tip angle 118 bodies 1
hole "Furo13" at (62.6173, 4, -112.8841) direction (0, -1, 0) diameter 2 depth 18 tip angle 118 bodies 1
hole "Furo14" at (38.6378, 4, -113.3276) direction (0, -1, 0) diameter 2 depth 18 tip angle 118 bodies 1

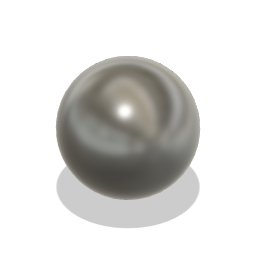
design "bola de resgate"
Autodesk Fusion 360 part; units mm, degrees
sketch "Esboço1" plane through (0, 0, 0) normal (0, 1, 0) x (1, 0, 0)
  ellipse E0 centre (0, 0) end of major axis (14, 20) minor radius 25
  line L0 (-14, -20) -> (14, 20) construction
  line L1 (20.4808, -14.3366) -> (-20.4808, 14.3366) construction
  dimension "d1" = 50
  constraint coincident E0 L0.start
  constraint coincident E0 L0.end
  constraint coincident E0 L1.start
  constraint coincident E0 L1.end
  constraint coincident E0.centre origin
sphere "Primitiva de esfera1" add diameter 50 placed x (1, 0, 0) y (0, 0, -1) z (0, 1, 0) at (0, 0, 0)

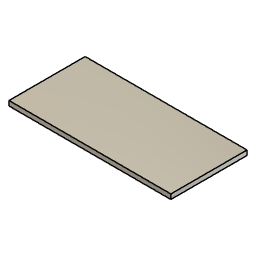
design "fita"
Autodesk Fusion 360 part; units mm, degrees
sketch "Esboço1" plane through (0, 0, 0) normal (0, 1, 0) x (1, 0, 0)
  line L0 (0, 0) -> (102, 0)
  line L1 (102, 0) -> (102, 48)
  line L2 (102, 48) -> (0, 48)
  line L3 (0, 48) -> (0, 0)
  dimension "d1" = 48
  dimension "d2" = 102
  constraint horizontal L0
  constraint vertical L1
  constraint horizontal L2
  constraint vertical L3
  constraint coincident L0.start L3.end
  measures "d1" distance of L0.start L2.end
  measures "d2" distance of L0.start L0.end
extrude "Extrusão1" add sketch "Esboço1" along normal blind 3

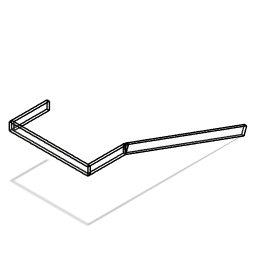
design "garra"
Autodesk Fusion 360 part; units mm, degrees
sketch "Esboço1" plane through (0, 0, 0) normal (0, 1, 0) x (1, 0, 0)
  line L0 (0, 0) -> (116.67, 109.4903)
  line L1 (0, 0) -> (9.9269, 1.2066)
  line L2 (9.9269, 1.2066) -> (126.5969, 110.6969)
  line L3 (116.67, 109.4903) -> (126.5969, 110.6969)
  dimension "d2" = 160
  dimension "d3" = 10
  dimension "d4" = 160
  constraint coincident L0.start L1.start
  constraint parallel L0 L2
  measures "d2" distance of L0.start L0.end
  measures "d3" distance of L0.start L1.end
  measures "d4" distance of L1.end L2.end
sketch "Esboço2" plane through (0, 0, 0) normal (0, 1, 0) x (1, 0, 0)
  line L0 (0, 0) -> (50, 0)
  line L1 (50, 0) -> (55.3888, 8.4238)
  line L2 (55.3888, 8.4238) -> (0, 8.4238)
  line L3 (0, 8.4238) -> (0, 0)
  dimension "d8" = 50
  dimension "d9" = 10
  constraint coincident L0.start L3.end
  constraint horizontal L0
  constraint horizontal L2
  constraint perpendicular L0 L3
  measures "d8" distance of L0.start L0.end
  measures "d9" distance of L0.end L1.end
sketch "Esboço3" plane through (0, 0, 0) normal (0, 1, 0) x (1, 0, 0)
  line L0 (0, 0) -> (100, 0)
  line L1 (0, 0) -> (0, 10)
  line L2 (100, 0) -> (100, 10)
  line L3 (0, 10) -> (100, 10)
  dimension "d12" = 100
  dimension "d13" = 10
  dimension "d14" = 10
  constraint coincident L0.start L1.start
  constraint horizontal L0
  constraint perpendicular L0 L1
  constraint perpendicular L0 L2
  measures "d12" distance of L0.start L0.end
  measures "d13" distance of L0.start L1.end
  measures "d14" distance of L0.end L2.end
extrude "Extrusão3" add sketch "Esboço3" along normal blind 3 makes body 1
move_body "Mover9" bodies 1 to x (1, 0, 0) y (0, 0, -1) z (0, 1, 0) at (0, 10, -10)
sketch "Esboço4" plane through (0, 0, 0) normal (0, 1, 0) x (1, 0, 0)
  line L0 (100, 20) -> (90, 20)
  line L1 (90, 20) -> (90, 65)
  line L2 (100, 20) -> (100, 65)
  line L3 (100, 65) -> (90, 65)
  line L4 (69.8794, 65) -> (59.8794, 65)
  line L5 (69.8794, 20) -> (59.8794, 20)
  line L6 (69.8794, 20) -> (69.8794, 65)
  line L7 (59.8794, 65) -> (59.8794, 20)
  dimension "d17" = 45
  dimension "d18" = 45
  dimension "d19" = 45
  dimension "d20" = 45
  constraint horizontal L0
  constraint perpendicular L0 L1
  constraint perpendicular L0 L2
  constraint horizontal L5
  constraint perpendicular L5 L6
  constraint perpendicular L5 L7
  measures "d17" distance of L0.end L1.end
  measures "d18" distance of L0.start L2.end
  measures "d19" distance of L5.end L4.end
  measures "d20" distance of L5.start L4.start
extrude "Extrusão4" add sketch "Esboço4" along normal blind 3 separate body contours L0 L1 L2 L3 makes body 2
extrude "Extrusão5" add sketch "Esboço4" along normal blind 3 separate body contours L4 L5 L6 L7 makes body 3
move_body "Mover10" bodies 3 to x (0, 1, 0) y (-1, 0, 0) z (0, 0, 1) at (2.9332, -59.8794, 6.9691)
move_body "Mover11" bodies 2 to x (0, 1, 0) y (-1, 0, 0) z (0, 0, 1) at (100.0082, -89.9667, 6.994)
move_body "Mover12" bodies 3 to x (1, 0, 0) y (0, 1, 0) z (0, 0, 1) at (0.0334, 0, 0)
move_body "Mover13" bodies 3 to x (1, 0, 0) y (0, 1, 0) z (0, 0, 1) at (0.0296, 0, 0.0296)
sketch "Esboço5" plane through (0, 0, 0) normal (0, 1, 0) x (1, 0, 0)
  line L0 (80, 60) -> (70, 60)
  line L1 (70, 60) -> (70, 220)
  line L2 (80, 60) -> (80, 220)
  line L3 (80, 220) -> (70, 220)
  dimension "d25" = 160
  dimension "d26" = 160
  constraint horizontal L0
  constraint perpendicular L0 L1
  constraint perpendicular L0 L2
  measures "d25" distance of L0.end L1.end
  measures "d26" distance of L0.start L2.end
extrude "Extrusão6" add sketch "Esboço5" along normal blind 3 separate body makes body 4
move_body "Mover14" bodies 4 to x (0, 0.939693, -0.34202) y (-1, 0, 0) z (0, 0.34202, 0.939693) at (98.7213, 8.9907, 13.3573)
move_body "Mover15" bodies 2 3 1 to x (1, 0, 0) y (0, 1, 0) z (0, 0, 1) at (-0.3286, 54.2931, -9.2119)
move_body "Mover16" bodies 3 1 2 to x (1, 0, 0) y (0, 1, 0) z (0, 0, 1) at (-0.9237, 0.0821, 0.2788)
sketch "Esboço6" plane through (0, 0, 0) normal (1, 0, 0) x (0, 0, -1)
  line L0 (66.746, 64.4054, -7.9114) -> (70.2133, 63.6454, -7.9114)
  line L1 (70.2133, 63.6454, -7.9114) -> (66.746, 54.3361, -7.9114)
  line L2 (66.746, 54.3361, -7.9114) -> (66.746, 64.4054, -7.9114)
extrude "Extrusão7" add sketch "Esboço6" along normal blind 3 separate body contours L0 L1 L2 in plane through (-7.9114, 0, 0) normal (1, 0, 0) makes body 5
move_body "Mover17" bodies 5 to x (1, 0, 0) y (0, 1, 0) z (0, 0, 1) at (103.673, 0.056, -0.2327)
copy_body "Corpo -> Componente1" bodies 5 removing the originals makes body 6 in component "Component"
copy_body "Corpo -> Componente2" bodies 4 removing the originals makes body 7 in component "Component'"
copy_body "Corpo -> Componente3" bodies 3 removing the originals makes body 8 in component "Component''"
copy_body "Corpo -> Componente4" bodies 2 removing the originals makes body 9 in component "Component'''"
copy_body "Corpo -> Componente5" bodies 1 removing the originals makes body 10 in component "Component''''"
sketch "Esboço7" plane through (0, 0, 0) normal (0, 1, 0) x (1, 0, 0)
component "Component" placed x (1, 0, 0) y (0, 1, 0) z (0, 0, 1) at (0, 0, 0)
component "Component'" placed x (1, 0, 0) y (0, 1, 0) z (0, 0, 1) at (0, 0, 0)
component "Component''" placed x (1, 0, 0) y (0, 1, 0) z (0, 0, 1) at (0, 0, 0)
component "Component'''" placed x (1, 0, 0) y (0, 1, 0) z (0, 0, 1) at (0, 0, 0)
component "Component''''" placed x (1, 0, 0) y (0, 1, 0) z (0, 0, 1) at (0, 0, 0)
